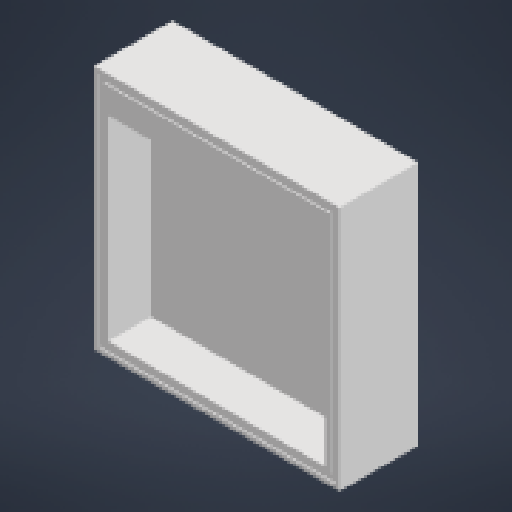
# Autodesk Inventor part: scd40holder
Saved by Autodesk Inventor 2026.1 (Build 301233020, 233B)
## iProperties
Created: 2026-06-04
Part Number: scd40holder
Material: Générique
Document SubType Name: Modeling
Designer: matpo
Density: 1 g/cm^3
Appearance: Par défaut
Author: matpo
Autodesk Inventor part; units mm, degrees
ref_plane "YZ Plane" through (0, 0, 0) normal (1, 0, 0) x (0, 1, 0)
sketch "Esquisse1" plane through (0, 0, 0) normal (0, 0, 1) x (1, 0, 0)
  line L0 (-20, 25.0501) -> (-10, 25.0501)
  line L1 (-20, -20) -> (-20, 25.0501)
  line L2 (20, -20) -> (-20, -20)
  line L3 (20, 20) -> (20, -20)
  line L4 (-10, 20) -> (20, 20)
  line L5 (-10, 25.0501) -> (-10, 20)
  line L6 (-10, 20) -> (-20, 20)
  line L7 (-10, 17.2) -> (17.2, 17.2)
  line L8 (17.2, 17.2) -> (17.2, -17.2)
  line L9 (17.2, -17.2) -> (-17.2, -17.2)
  line L10 (-17.2, -17.2) -> (-17.2, 17.2)
  line L11 (-10, 17.2) -> (-17.2, 17.2)
  point P0 (0, 0)
  dimension "d0" = 2.8
  dimension "d1" = 2.8
  constraints: 24 end point, 1 parallel, 1 perpendicular, 1 point on line, 2 other
  measures "d0" distance between parallel lines of L1 L10
  measures "d1" distance between parallel lines of L6 L11
ref_plane "Plan de construction1" through (-46.6, -47.5, 13) normal (0, 0, 1) x (1, 0, 0)
ref_plane "Plan de construction2" through (-20.1611, -20.1431, 4) normal (0, 0, 1) x (1, 0, 0)
extrude "Extrusion1" add sketch "Esquisse1" along normal blind 9 from surface at 4 contours L7 L8 L9 L10 L11
sketch "Esquisse2" plane through (-17.2, 17.2, 11) normal (0, 0, 1) x (1, 0, 0)
  line L0 (0, 0) -> (0, -34.4) projected
  line L1 (0, -34.4) -> (34.4, -34.4) projected
  line L2 (34.4, -34.4) -> (34.4, 0) projected
  line L3 (34.4, 0) -> (0, 0) projected
  line L4 (2, -2) -> (2, -32.4)
  line L5 (2, -32.4) -> (32.4, -32.4)
  line L6 (32.4, -32.4) -> (32.4, -2)
  line L7 (32.4, -2) -> (2, -2)
  point P0 (17.2, -17.2)
  dimension "d7" = 2
  constraints: 8 end point, 3 other
  measures "d7" distance between parallel lines of L3 L7
extrude "Extrusion2" [suppressed]
sketch "Esquisse3" plane through (-15.2, 15.2, 11) normal (0, -1, 0) x (1, 0, 0)
  line L0 (5.2, 2) -> (5.2, -7) projected
  point P0 (15.2, -11)
extrude "Extrusion3" [suppressed]
sketch "Esquisse5" plane through (-15.2, -15.2, 2) normal (0, 0, 1) x (1, 0, 0)
  line L0 (30.4, 30.4) -> (30.4, 0) projected
  line L1 (0, 30.4) -> (30.4, 30.4) projected
  line L2 (0, 0) -> (0, 30.4) projected
  line L3 (30.4, 0) -> (0, 0) projected
  line L4 (6.5, 20.4) -> (28.1, 20.4) construction
  line L5 (28.1, 20.4) -> (28.1, 7) construction
  line L6 (28.1, 7) -> (6.5, 7) construction
  line L7 (6.5, 7) -> (6.5, 20.4) construction
  line L8 (6.5, 20.4) -> (28.1, 7) construction
  line L9 (28.1, 20.4) -> (6.5, 7) construction
  line L10 (28.4, 20.7) -> (6.2, 20.7)
  line L11 (6.2, 20.7) -> (6.2, 6.7) construction
  line L12 (6.2, 6.7) -> (28.4, 6.7)
  line L13 (28.4, 6.7) -> (28.4, 20.7)
  line L14 (5.2, 30.4) -> (6.2, 20.7)
  line L15 (6.2, 6.7) -> (0, 6.7)
  point P0 (15.2, 15.2)
  point P1 (17.3, 13.7)
  dimension "d14" = 21.6
  dimension "d15" = 13.4
  dimension "d16" = 2.3
  dimension "d17" = 10
  dimension "d18" = 0.3
  constraints: 24 end point, 4 parallel, 2 horizontal, 2 midpoint, 2 perpendicular, 1 point on line, 3 other
  measures "d14" distance of L5.end L6.end
  measures "d15" distance of L4.end L5.end
  measures "d16" distance between parallel lines of L0 L5
  measures "d17" distance between parallel lines of L1 L4
  measures "d18" distance between parallel lines of L4 L10
extrude "Extrusion5" [suppressed]
sketch "Esquisse6" plane through (0, 0, 11) normal (0, 0, 1) x (1, 0, 0)
  line L0 (-15.8, -15.8) -> (-15.8, 15.8) projected
  line L1 (-16.6, 16.6) -> (-16.6, -16.6) projected
  line L2 (15.8, -15.8) -> (-15.8, -15.8) projected
  line L3 (16.6, -16.6) -> (-16.6, -16.6) projected
  line L4 (16.6, -16.6) -> (16.6, 16.6) projected
  line L5 (15.8, 15.8) -> (15.8, -15.8) projected
  line L6 (16.6, 16.6) -> (-16.6, 16.6) projected
  line L7 (-15.8, 15.8) -> (15.8, 15.8) projected
  point P0 (0, 0)
  constraints: 1 other
extrude "Extrusion6" [suppressed]
sketch "Esquisse7" plane through (-15.2, 15.2, 11) normal (0, -1, 0) x (1, 0, 0)
  line L0 (0, -6) -> (30.4, -6) projected
  line L1 (30.4, -6) -> (30.4, 0) projected
  line L2 (0, 0) -> (30.4, 0) projected
  line L3 (0, -6) -> (0, 0) projected
  point P0 (15.2, -11)
extrude "Extrusion7" [suppressed]
equation "\"d0\" = d1"
